Autodesk Fusion 360 part; units mm, degrees
(part 13 of 28)
  line L4632 (91.6329, 89.3668) -> (91.4774, 89.2538)
  line L4633 (91.4774, 89.2538) -> (91.3062, 89.1666)
  line L4634 (91.3062, 89.1666) -> (91.1233, 89.1072)
  line L4635 (91.1233, 89.1072) -> (90.9335, 89.0771)
  line L4636 (90.9335, 89.0771) -> (90.7413, 89.0771)
  line L4637 (90.7413, 89.0771) -> (90.5514, 89.1072)
  line L4638 (90.5514, 89.1072) -> (90.3686, 89.1666)
  line L4639 (90.3686, 89.1666) -> (90.1973, 89.2538)
  line L4640 (90.1973, 89.2538) -> (90.0418, 89.3668)
  line L4641 (90.0418, 89.3668) -> (89.9059, 89.5027)
  line L4642 (89.9059, 89.5027) -> (89.8261, 89.6126)
  line L4643 (89.8261, 89.6126) -> (84.5942, 84.3807)
  line L4644 (84.5942, 84.3807) -> (84.5942, 82.7886)
  line L4645 (84.5942, 82.7886) -> (84.7225, 82.7469)
  line L4646 (84.7225, 82.7469) -> (84.8973, 82.6578)
  line L4647 (84.8973, 82.6578) -> (85.056, 82.5425)
  line L4648 (85.056, 82.5425) -> (85.1947, 82.4038)
  line L4649 (85.1947, 82.4038) -> (85.31, 82.2452)
  line L4650 (85.31, 82.2452) -> (85.399, 82.0704)
  line L4651 (85.399, 82.0704) -> (85.4596, 81.8838)
  line L4652 (85.4596, 81.8838) -> (85.4903, 81.6901)
  line L4653 (85.4903, 81.6901) -> (85.4903, 81.494)
  line L4654 (85.4903, 81.494) -> (85.4596, 81.3002)
  line L4655 (85.4596, 81.3002) -> (85.399, 81.1137)
  line L4656 (85.399, 81.1137) -> (85.31, 80.9389)
  line L4657 (85.31, 80.9389) -> (85.1947, 80.7802)
  line L4658 (85.1947, 80.7802) -> (85.056, 80.6415)
  line L4659 (85.056, 80.6415) -> (84.8973, 80.5262)
  line L4660 (84.8973, 80.5262) -> (84.7225, 80.4372)
  line L4661 (84.7225, 80.4372) -> (84.536, 80.3766)
  line L4662 (84.536, 80.3766) -> (84.3423, 80.3459)
  line L4663 (84.3423, 80.3459) -> (84.2442, 80.342)
  line L4664 (84.2442, 80.342) -> (83.7442, 80.342)
  line L4665 (83.7442, 80.342) -> (83.6461, 80.3459)
  line L4666 (83.6461, 80.3459) -> (83.4524, 80.3766)
  line L4667 (83.4524, 80.3766) -> (83.2658, 80.4372)
  line L4668 (83.2658, 80.4372) -> (83.0911, 80.5262)
  line L4669 (83.0911, 80.5262) -> (82.9324, 80.6415)
  line L4670 (82.9324, 80.6415) -> (82.7937, 80.7802)
  line L4671 (82.7937, 80.7802) -> (82.6784, 80.9389)
  line L4672 (82.6784, 80.9389) -> (82.5893, 81.1137)
  line L4673 (82.5893, 81.1137) -> (82.5287, 81.3002)
  line L4674 (82.5287, 81.3002) -> (82.498, 81.494)
  line L4675 (82.498, 81.494) -> (82.498, 81.6901)
  line L4676 (82.498, 81.6901) -> (82.5287, 81.8838)
  line L4677 (82.5287, 81.8838) -> (82.5893, 82.0704)
  line L4678 (82.5893, 82.0704) -> (82.6784, 82.2452)
  line L4679 (82.6784, 82.2452) -> (82.7937, 82.4038)
  line L4680 (82.7937, 82.4038) -> (82.9324, 82.5425)
  line L4681 (82.9324, 82.5425) -> (83.0911, 82.6578)
  line L4682 (83.0911, 82.6578) -> (83.2658, 82.7469)
  line L4683 (83.2658, 82.7469) -> (83.3942, 82.7886)
  line L4684 (83.3942, 82.7886) -> (83.3942, 84.6292)
  line L4685 (83.3942, 84.6292) -> (83.3993, 84.7075)
  line L4686 (83.3993, 84.7075) -> (83.4399, 84.8588)
  line L4687 (83.4399, 84.8588) -> (83.5182, 84.9944)
  line L4688 (83.5182, 84.9944) -> (83.5699, 85.0535)
  line L4689 (83.5699, 85.0535) -> (89.514, 90.9976)
  line L4690 (89.514, 90.9976) -> (89.5731, 91.0493)
  line L4691 (89.5731, 91.0493) -> (89.6388, 91.0873)
  line L4692 (89.6388, 91.0873) -> (89.6462, 91.1343)
  line L4693 (89.6462, 91.1343) -> (89.7056, 91.3171)
  line L4694 (89.7056, 91.3171) -> (89.7929, 91.4884)
  line L4695 (89.7929, 91.4884) -> (89.9059, 91.6439)
  line L4696 (89.9059, 91.6439) -> (90.0418, 91.7798)
  line L4697 (90.0418, 91.7798) -> (90.1973, 91.8928)
  line L4698 (90.1973, 91.8928) -> (90.3686, 91.9801)
  line L4699 (90.3686, 91.9801) -> (90.5514, 92.0395)
  line L4700 (90.5514, 92.0395) -> (90.7413, 92.0695)
  line L4701 (90.7413, 92.0695) -> (90.9335, 92.0695)
  line L4702 (90.9335, 92.0695) -> (91.1233, 92.0395)
  line L4703 (126.0483, 92.0395) -> (126.2312, 91.9801)
  line L4704 (126.2312, 91.9801) -> (126.4024, 91.8928)
  line L4705 (126.4024, 91.8928) -> (126.5579, 91.7798)
  line L4706 (126.5579, 91.7798) -> (126.6939, 91.6439)
  line L4707 (126.6939, 91.6439) -> (126.8069, 91.4884)
  line L4708 (126.8069, 91.4884) -> (126.8941, 91.3171)
  line L4709 (126.8941, 91.3171) -> (126.9535, 91.1343)
  line L4710 (126.9535, 91.1343) -> (126.9836, 90.9444)
  line L4711 (126.9836, 90.9444) -> (126.9874, 90.8483)
  line L4712 (126.9874, 90.8483) -> (126.9874, 90.2983)
  line L4713 (126.9874, 90.2983) -> (126.9836, 90.2022)
  line L4714 (126.9836, 90.2022) -> (126.9535, 90.0123)
  line L4715 (126.9535, 90.0123) -> (126.8941, 89.8295)
  line L4716 (126.8941, 89.8295) -> (126.8069, 89.6583)
  line L4717 (126.8069, 89.6583) -> (126.6939, 89.5027)
  line L4718 (126.6939, 89.5027) -> (126.5579, 89.3668)
  line L4719 (126.5579, 89.3668) -> (126.4024, 89.2538)
  line L4720 (126.4024, 89.2538) -> (126.2312, 89.1666)
  line L4721 (126.2312, 89.1666) -> (126.0483, 89.1072)
  line L4722 (126.0483, 89.1072) -> (125.8585, 89.0771)
  line L4723 (125.8585, 89.0771) -> (125.6663, 89.0771)
  line L4724 (125.6663, 89.0771) -> (125.4764, 89.1072)
  line L4725 (125.4764, 89.1072) -> (125.2936, 89.1666)
  line L4726 (125.2936, 89.1666) -> (125.1223, 89.2538)
  line L4727 (125.1223, 89.2538) -> (124.9668, 89.3668)
  line L4728 (124.9668, 89.3668) -> (124.8309, 89.5027)
  line L4729 (124.8309, 89.5027) -> (124.7511, 89.6126)
  line L4730 (124.7511, 89.6126) -> (119.5192, 84.3807)
  line L4731 (119.5192, 84.3807) -> (119.5192, 82.7886)
  line L4732 (119.5192, 82.7886) -> (119.6475, 82.7469)
  line L4733 (119.6475, 82.7469) -> (119.8223, 82.6578)
  line L4734 (119.8223, 82.6578) -> (119.981, 82.5425)
  line L4735 (119.981, 82.5425) -> (120.1197, 82.4038)
  line L4736 (120.1197, 82.4038) -> (120.235, 82.2452)
  line L4737 (120.235, 82.2452) -> (120.324, 82.0704)
  line L4738 (120.324, 82.0704) -> (120.3846, 81.8838)
  line L4739 (120.3846, 81.8838) -> (120.4153, 81.6901)
  line L4740 (120.4153, 81.6901) -> (120.4153, 81.494)
  line L4741 (120.4153, 81.494) -> (120.3846, 81.3002)
  line L4742 (120.3846, 81.3002) -> (120.324, 81.1137)
  line L4743 (120.324, 81.1137) -> (120.235, 80.9389)
  line L4744 (120.235, 80.9389) -> (120.1197, 80.7802)
  line L4745 (120.1197, 80.7802) -> (119.981, 80.6415)
  line L4746 (119.981, 80.6415) -> (119.8223, 80.5262)
  line L4747 (119.8223, 80.5262) -> (119.6475, 80.4372)
  line L4748 (119.6475, 80.4372) -> (119.461, 80.3766)
  line L4749 (119.461, 80.3766) -> (119.2673, 80.3459)
  line L4750 (119.2673, 80.3459) -> (119.1692, 80.342)
  line L4751 (119.1692, 80.342) -> (118.6692, 80.342)
  line L4752 (118.6692, 80.342) -> (118.5711, 80.3459)
  line L4753 (118.5711, 80.3459) -> (118.3774, 80.3766)
  line L4754 (118.3774, 80.3766) -> (118.1908, 80.4372)
  line L4755 (118.1908, 80.4372) -> (118.0161, 80.5262)
  line L4756 (118.0161, 80.5262) -> (117.8574, 80.6415)
  line L4757 (117.8574, 80.6415) -> (117.7187, 80.7802)
  line L4758 (117.7187, 80.7802) -> (117.6034, 80.9389)
  line L4759 (117.6034, 80.9389) -> (117.5143, 81.1137)
  line L4760 (117.5143, 81.1137) -> (117.4537, 81.3002)
  line L4761 (117.4537, 81.3002) -> (117.423, 81.494)
  line L4762 (117.423, 81.494) -> (117.423, 81.6901)
  line L4763 (117.423, 81.6901) -> (117.4537, 81.8838)
  line L4764 (117.4537, 81.8838) -> (117.5143, 82.0704)
  line L4765 (117.5143, 82.0704) -> (117.6034, 82.2452)
  line L4766 (117.6034, 82.2452) -> (117.7187, 82.4038)
  line L4767 (117.7187, 82.4038) -> (117.8574, 82.5425)
  line L4768 (117.8574, 82.5425) -> (118.0161, 82.6578)
  line L4769 (118.0161, 82.6578) -> (118.1908, 82.7469)
  line L4770 (118.1908, 82.7469) -> (118.3192, 82.7886)
  line L4771 (118.3192, 82.7886) -> (118.3192, 84.6292)
  line L4772 (118.3192, 84.6292) -> (118.3243, 84.7075)
  line L4773 (118.3243, 84.7075) -> (118.3649, 84.8588)
  line L4774 (118.3649, 84.8588) -> (118.4432, 84.9944)
  line L4775 (118.4432, 84.9944) -> (118.4949, 85.0535)
  line L4776 (118.4949, 85.0535) -> (124.439, 90.9976)
  line L4777 (124.439, 90.9976) -> (124.4981, 91.0493)
  line L4778 (124.4981, 91.0493) -> (124.5638, 91.0873)
  line L4779 (124.5638, 91.0873) -> (124.5712, 91.1343)
  line L4780 (124.5712, 91.1343) -> (124.6306, 91.3171)
  line L4781 (124.6306, 91.3171) -> (124.7179, 91.4884)
  line L4782 (124.7179, 91.4884) -> (124.8309, 91.6439)
  line L4783 (124.8309, 91.6439) -> (124.9668, 91.7798)
  line L4784 (124.9668, 91.7798) -> (125.1223, 91.8928)
  line L4785 (125.1223, 91.8928) -> (125.2936, 91.9801)
  line L4786 (125.2936, 91.9801) -> (125.4764, 92.0395)
  line L4787 (125.4764, 92.0395) -> (125.6663, 92.0695)
  line L4788 (125.6663, 92.0695) -> (125.8585, 92.0695)
  line L4789 (125.8585, 92.0695) -> (126.0483, 92.0395)
  line L4790 (0.0231, 6.9946) -> (0.025, 6.985)
  line L4791 (0.025, 6.985) -> (0.025, 0.025)
  line L4792 (0.025, 0.025) -> (7.62, 0.025)
  line L4793 (7.62, 0.025) -> (7.6296, 0.0231)
  line L4794 (7.6296, 0.0231) -> (7.6431, 0.0096)
  line L4795 (7.6431, 0.0096) -> (7.6431, -0.0096)
  line L4796 (7.6431, -0.0096) -> (7.6296, -0.0231)
  line L4797 (7.6296, -0.0231) -> (7.62, -0.025)
  line L4798 (7.62, -0.025) -> (0.025, -0.025)
  line L4799 (0.025, -0.025) -> (0.025, -5.08)
  line L4800 (0.025, -5.08) -> (0.0231, -5.0896)
  line L4801 (0.0231, -5.0896) -> (0.0096, -5.1031)
  line L4802 (0.0096, -5.1031) -> (-0.0096, -5.1031)
  line L4803 (-0.0096, -5.1031) -> (-0.0231, -5.0896)
  line L4804 (-0.0231, -5.0896) -> (-0.025, -5.08)
  line L4805 (-0.025, -5.08) -> (-0.025, -0.025)
  line L4806 (-0.025, -0.025) -> (-5.08, -0.025)
  line L4807 (-5.08, -0.025) -> (-5.0896, -0.0231)
  line L4808 (-5.0896, -0.0231) -> (-5.1031, -0.0096)
  line L4809 (-5.1031, -0.0096) -> (-5.1031, 0.0096)
  line L4810 (-5.1031, 0.0096) -> (-5.0896, 0.0231)
  line L4811 (-5.0896, 0.0231) -> (-5.08, 0.025)
  line L4812 (-5.08, 0.025) -> (-0.025, 0.025)
  line L4813 (-0.025, 0.025) -> (-0.025, 6.985)
  line L4814 (-0.025, 6.985) -> (-0.0231, 6.9946)
  line L4815 (-0.0231, 6.9946) -> (-0.0096, 7.0081)
  line L4816 (-0.0096, 7.0081) -> (0.0096, 7.0081)
  line L4817 (0.0096, 7.0081) -> (0.0231, 6.9946)
  line L4818 (66.04, 36.855) -> (66.0496, 36.8531)
  line L4819 (66.0496, 36.8531) -> (66.0631, 36.8396)
  line L4820 (66.0631, 36.8396) -> (66.065, 36.83)
  line L4821 (66.065, 36.83) -> (66.065, 5.08)
  line L4822 (66.065, 5.08) -> (66.0631, 5.0704)
  line L4823 (66.0631, 5.0704) -> (66.0496, 5.0569)
  line L4824 (66.0496, 5.0569) -> (66.04, 5.055)
  line L4825 (66.04, 5.055) -> (8.255, 5.055)
  line L4826 (8.255, 5.055) -> (8.2454, 5.0569)
  line L4827 (8.2454, 5.0569) -> (8.2319, 5.0704)
  line L4828 (8.2319, 5.0704) -> (8.23, 5.08)
  line L4829 (8.23, 5.08) -> (8.23, 36.83)
  line L4830 (8.23, 36.83) -> (8.2319, 36.8396)
  line L4831 (8.2319, 36.8396) -> (8.2454, 36.8531)
  line L4832 (8.2454, 36.8531) -> (8.255, 36.855)
  line L4833 (8.255, 36.855) -> (66.04, 36.855)
  line L4834 (8.28, 36.805) -> (8.28, 5.105)
  line L4835 (8.28, 5.105) -> (66.015, 5.105)
  line L4836 (66.015, 5.105) -> (66.015, 36.805)
  line L4837 (66.015, 36.805) -> (62.865, 36.805)
  line L4838 (62.865, 36.805) -> (8.28, 36.805)
  line L4839 (127, 36.855) -> (127.0096, 36.8531)
  line L4840 (127.0096, 36.8531) -> (127.0231, 36.8396)
  line L4841 (127.0231, 36.8396) -> (127.025, 36.83)
  line L4842 (127.025, 36.83) -> (127.025, 5.08)
  line L4843 (127.025, 5.08) -> (127.0231, 5.0704)
  line L4844 (127.0231, 5.0704) -> (127.0096, 5.0569)
  line L4845 (127.0096, 5.0569) -> (127, 5.055)
  line L4846 (127, 5.055) -> (69.215, 5.055)
  line L4847 (69.215, 5.055) -> (69.2054, 5.0569)
  line L4848 (69.2054, 5.0569) -> (69.1919, 5.0704)
  line L4849 (69.1919, 5.0704) -> (69.19, 5.08)
  line L4850 (69.19, 5.08) -> (69.19, 36.83)
  line L4851 (69.19, 36.83) -> (69.1919, 36.8396)
  line L4852 (69.1919, 36.8396) -> (69.2054, 36.8531)
  line L4853 (69.2054, 36.8531) -> (69.215, 36.855)
  line L4854 (69.215, 36.855) -> (127, 36.855)
  line L4855 (69.24, 36.805) -> (69.24, 5.105)
  line L4856 (69.24, 5.105) -> (126.975, 5.105)
  line L4857 (126.975, 5.105) -> (126.975, 36.805)
  line L4858 (126.975, 36.805) -> (123.825, 36.805)
  line L4859 (123.825, 36.805) -> (69.24, 36.805)
  line L4860 (43.18, 97.815) -> (74.93, 97.815)
  line L4861 (74.93, 97.815) -> (74.9396, 97.8131)
  line L4862 (74.9396, 97.8131) -> (74.9531, 97.7996)
  line L4863 (74.9531, 97.7996) -> (74.955, 97.79)
  line L4864 (74.955, 97.79) -> (74.955, 40.005)
  line L4865 (74.955, 40.005) -> (74.9531, 39.9954)
  line L4866 (74.9531, 39.9954) -> (74.9396, 39.9819)
  line L4867 (74.9396, 39.9819) -> (74.93, 39.98)
  line L4868 (74.93, 39.98) -> (43.18, 39.98)
  line L4869 (43.18, 39.98) -> (43.1704, 39.9819)
  line L4870 (43.1704, 39.9819) -> (43.1569, 39.9954)
  line L4871 (43.1569, 39.9954) -> (43.155, 40.005)
  line L4872 (43.155, 40.005) -> (43.155, 97.765)
  line L4873 (40.03, 97.765) -> (40.03, 40.005)
  line L4874 (40.03, 40.005) -> (40.0281, 39.9954)
  line L4875 (40.0281, 39.9954) -> (40.0146, 39.9819)
  line L4876 (40.0146, 39.9819) -> (40.005, 39.98)
  line L4877 (40.005, 39.98) -> (8.255, 39.98)
  line L4878 (8.255, 39.98) -> (8.2454, 39.9819)
  line L4879 (8.2454, 39.9819) -> (8.2319, 39.9954)
  line L4880 (8.2319, 39.9954) -> (8.23, 40.005)
  line L4881 (8.23, 40.005) -> (8.23, 97.79)
  line L4882 (8.23, 97.79) -> (8.2319, 97.7996)
  line L4883 (8.2319, 97.7996) -> (8.2454, 97.8131)
  line L4884 (8.2454, 97.8131) -> (8.255, 97.815)
  line L4885 (8.255, 97.815) -> (40.005, 97.815)
  line L4886 (43.205, 97.765) -> (43.205, 40.03)
  line L4887 (43.205, 40.03) -> (74.905, 40.03)
  line L4888 (74.905, 40.03) -> (74.905, 97.765)
  line L4889 (74.905, 97.765) -> (43.205, 97.765)
  line L4890 (8.28, 97.765) -> (8.28, 40.03)
  line L4891 (8.28, 40.03) -> (39.98, 40.03)
  line L4892 (39.98, 40.03) -> (39.98, 97.765)
  line L4893 (39.98, 97.765) -> (8.28, 97.765)
  line L4894 (109.8646, 97.8131) -> (109.8781, 97.7996)
  line L4895 (109.8781, 97.7996) -> (109.88, 97.79)
  line L4896 (109.88, 97.79) -> (109.88, 40.005)
  line L4897 (109.88, 40.005) -> (109.8781, 39.9954)
  line L4898 (109.8781, 39.9954) -> (109.8646, 39.9819)
  line L4899 (109.8646, 39.9819) -> (109.855, 39.98)
  line L4900 (109.855, 39.98) -> (78.105, 39.98)
  line L4901 (78.105, 39.98) -> (78.0954, 39.9819)
  line L4902 (78.0954, 39.9819) -> (78.0819, 39.9954)
  line L4903 (78.0819, 39.9954) -> (78.08, 40.005)
  line L4904 (78.08, 40.005) -> (78.08, 97.79)
  line L4905 (78.08, 97.79) -> (78.0819, 97.7996)
  line L4906 (78.0819, 97.7996) -> (78.0954, 97.8131)
  line L4907 (78.0954, 97.8131) -> (78.105, 97.815)
  line L4908 (78.105, 97.815) -> (109.855, 97.815)
  line L4909 (109.855, 97.815) -> (109.8646, 97.8131)
  line L4910 (78.13, 97.765) -> (78.13, 40.03)
  line L4911 (78.13, 40.03) -> (109.83, 40.03)
  line L4912 (109.83, 40.03) -> (109.83, 97.765)
  line L4913 (109.83, 97.765) -> (78.13, 97.765)
  line L4914 (144.7896, 97.8131) -> (144.8031, 97.7996)
  line L4915 (144.8031, 97.7996) -> (144.805, 97.79)
  line L4916 (144.805, 97.79) -> (144.805, 40.005)
  line L4917 (144.805, 40.005) -> (144.8031, 39.9954)
  line L4918 (144.8031, 39.9954) -> (144.7896, 39.9819)
  line L4919 (144.7896, 39.9819) -> (144.78, 39.98)
  line L4920 (144.78, 39.98) -> (113.03, 39.98)
  line L4921 (113.03, 39.98) -> (113.0204, 39.9819)
  line L4922 (113.0204, 39.9819) -> (113.0069, 39.9954)
  line L4923 (113.0069, 39.9954) -> (113.005, 40.005)
  line L4924 (113.005, 40.005) -> (113.005, 97.79)
  line L4925 (113.005, 97.79) -> (113.0069, 97.7996)
  line L4926 (113.0069, 97.7996) -> (113.0204, 97.8131)
  line L4927 (113.0204, 97.8131) -> (113.03, 97.815)
  line L4928 (113.03, 97.815) -> (144.78, 97.815)
  line L4929 (144.78, 97.815) -> (144.7896, 97.8131)
  line L4930 (113.055, 97.765) -> (113.055, 40.03)
  line L4931 (113.055, 40.03) -> (144.755, 40.03)
  line L4932 (144.755, 40.03) -> (144.755, 97.765)
  line L4933 (144.755, 97.765) -> (113.055, 97.765)
  arc A0 (27.7068, 75.4403) -> (25.7164, 75.4403) centre (26.7116, 75.4403) ccw
  arc A1 (25.7116, 74.2403) -> (27.7116, 74.2403) centre (26.7116, 74.2403) ccw
  line L4934 (25.7116, 75.4403) -> (25.7164, 75.4403)
  line L4935 (27.7068, 75.4403) -> (27.7116, 75.4403)
  line L4936 (27.7068, 75.4403) -> (27.7116, 74.2403)
  line L4937 (25.7116, 74.2403) -> (25.7164, 75.4403)
  arc A2 (-14.9284, 74.2403) -> (-12.9284, 74.2403) centre (-13.9284, 74.2403) ccw
  line L4938 (-14.9284, 74.2403) -> (-14.9284, 75.4403)
  line L4939 (-12.9332, 75.4403) -> (-12.9284, 74.2403)
  arc A3 (-12.9332, 75.4403) -> (-14.9236, 75.4403) centre (-13.9284, 75.4403) ccw
  spline S0 degree 5 poles (-14.9236, 75.4403) (-14.9236, 75.4399) (-14.9237, 75.4393) (-14.9241, 75.4391) (-14.9252, 75.4396) (-14.9268, 75.4409) (-14.9279, 75.4415) (-14.9283, 75.4412) (-14.9284, 75.4407) (-14.9284, 75.4403) knots 0 0 0 0 0 0 0.2 0.4 0.6 0.8 1 1 1 1 1 1
  constraint perpendicular L2713 L4935
  constraint tangent L2829 A0
  constraint tangent L2820 A1
  constraint collinear L4934 L4935
  constraint coincident A0.centre L4934
  constraint tangent A2 L4938
  constraint tangent A3 S0
sketch "Blinking Light House-PTH-drl_map" plane through (0, 0, 1.4859) normal (0, 0, 1) x (1, 0, 0)
  line L0 (0, 0) -> (0, -5.08)
  line L1 (0, 0) -> (-5.08, 0)
  line L2 (0, 0) -> (7.62, 0)
  line L3 (0, 0) -> (0, 6.985)
  line L4 (123.825, 36.83) -> (127, 36.83)
  line L5 (127, 36.83) -> (127, 5.08)
  line L6 (69.215, 36.83) -> (127, 36.83)
  line L7 (127, 5.08) -> (69.215, 5.08)
  line L8 (69.215, 5.08) -> (69.215, 36.83)
  line L9 (62.865, 36.83) -> (66.04, 36.83)
  line L10 (66.04, 36.83) -> (66.04, 5.08)
  line L11 (8.255, 36.83) -> (66.04, 36.83)
  line L12 (8.255, 5.08) -> (8.255, 36.83)
  line L13 (66.04, 5.08) -> (8.255, 5.08)
  line L14 (113.03, 97.79) -> (144.78, 97.79)
  line L15 (113.03, 40.005) -> (113.03, 97.79)
  line L16 (144.78, 97.79) -> (144.78, 40.005)
  line L17 (144.78, 40.005) -> (113.03, 40.005)
  line L18 (109.855, 97.79) -> (109.855, 40.005)
  line L19 (78.105, 97.79) -> (109.855, 97.79)
  line L20 (109.855, 40.005) -> (78.105, 40.005)
  line L21 (78.105, 40.005) -> (78.105, 97.79)
  line L22 (43.18, 97.79) -> (74.93, 97.79)
  line L23 (74.93, 97.79) -> (74.93, 40.005)
  line L24 (74.93, 40.005) -> (43.18, 40.005)
  line L25 (40.005, 40.005) -> (8.255, 40.005)
  line L26 (43.18, 40.005) -> (43.18, 97.79)
  line L27 (40.005, 97.79) -> (43.18, 97.79)
  line L28 (8.255, 40.005) -> (8.255, 97.79)
  line L29 (40.005, 40.005) -> (8.255, 40.005)
  line L30 (40.005, 97.79) -> (40.005, 40.005)
  line L31 (8.255, 97.79) -> (40.005, 97.79)
  line L32 (-2.4972, -8.2198) -> (-2.4972, -6.2198)
  line L33 (-2.4972, -6.2198) -> (-2.021, -6.2198)
  line L34 (-2.021, -6.2198) -> (-1.7353, -6.3151)
  line L35 (-1.7353, -6.3151) -> (-1.5449, -6.5056)
  line L36 (-1.5449, -6.5056) -> (-1.4496, -6.696)
  line L37 (-1.4496, -6.696) -> (-1.3544, -7.077)
  line L38 (-1.3544, -7.077) -> (-1.3544, -7.3627)
  line L39 (-1.3544, -7.3627) -> (-1.4496, -7.7436)
  line L40 (-1.4496, -7.7436) -> (-1.5449, -7.9341)
  line L41 (-1.5449, -7.9341) -> (-1.7353, -8.1246)
  line L42 (-1.7353, -8.1246) -> (-2.021, -8.2198)
  line L43 (-2.021, -8.2198) -> (-2.4972, -8.2198)
  line L44 (-0.4972, -8.2198) -> (-0.4972, -6.8865)
  line L45 (-0.4972, -7.2675) -> (-0.402, -7.077)
  line L46 (-0.402, -7.077) -> (-0.3068, -6.9817)
  line L47 (-0.3068, -6.9817) -> (-0.1163, -6.8865)
  line L48 (-0.1163, -6.8865) -> (0.0742, -6.8865)
  line L49 (0.7409, -8.2198) -> (0.7409, -6.8865)
  line L50 (0.7409, -6.2198) -> (0.6456, -6.3151)
  line L51 (0.6456, -6.3151) -> (0.7409, -6.4103)
  line L52 (0.7409, -6.4103) -> (0.8361, -6.3151)
  line L53 (0.8361, -6.3151) -> (0.7409, -6.2198)
  line L54 (0.7409, -6.2198) -> (0.7409, -6.4103)
  line L55 (1.979, -8.2198) -> (1.7885, -8.1246)
  line L56 (1.7885, -8.1246) -> (1.6932, -7.9341)
  line L57 (1.6932, -7.9341) -> (1.6932, -6.2198)
  line L58 (3.0266, -8.2198) -> (2.8361, -8.1246)
  line L59 (2.8361, -8.1246) -> (2.7409, -7.9341)
  line L60 (2.7409, -7.9341) -> (2.7409, -6.2198)
  line L61 (5.3123, -8.2198) -> (5.3123, -6.2198)
  line L62 (5.3123, -6.2198) -> (5.979, -7.6484)
  line L63 (5.979, -7.6484) -> (6.6456, -6.2198)
  line L64 (6.6456, -6.2198) -> (6.6456, -8.2198)
  line L65 (8.4551, -8.2198) -> (8.4551, -7.1722)
  line L66 (8.4551, -7.1722) -> (8.3599, -6.9817)
  line L67 (8.3599, -6.9817) -> (8.1694, -6.8865)
  line L68 (8.1694, -6.8865) -> (7.7885, -6.8865)
  line L69 (7.7885, -6.8865) -> (7.598, -6.9817)
  line L70 (8.4551, -8.1246) -> (8.2647, -8.2198)
  line L71 (8.2647, -8.2198) -> (7.7885, -8.2198)
  line L72 (7.7885, -8.2198) -> (7.598, -8.1246)
  line L73 (7.598, -8.1246) -> (7.5028, -7.9341)
  line L74 (7.5028, -7.9341) -> (7.5028, -7.7436)
  line L75 (7.5028, -7.7436) -> (7.598, -7.5532)
  line L76 (7.598, -7.5532) -> (7.7885, -7.4579)
  line L77 (7.7885, -7.4579) -> (8.2647, -7.4579)
  line L78 (8.2647, -7.4579) -> (8.4551, -7.3627)
  line L79 (9.4075, -6.8865) -> (9.4075, -8.8865)
  line L80 (9.4075, -6.9817) -> (9.598, -6.8865)
  line L81 (9.598, -6.8865) -> (9.979, -6.8865)
  line L82 (9.979, -6.8865) -> (10.1694, -6.9817)
  line L83 (10.1694, -6.9817) -> (10.2647, -7.077)
  line L84 (10.2647, -7.077) -> (10.3599, -7.2675)
  line L85 (10.3599, -7.2675) -> (10.3599, -7.8389)
  line L86 (10.3599, -7.8389) -> (10.2647, -8.0294)
  line L87 (10.2647, -8.0294) -> (10.1694, -8.1246)
  line L88 (10.1694, -8.1246) -> (9.979, -8.2198)
  line L89 (9.979, -8.2198) -> (9.598, -8.2198)
  line L90 (9.598, -8.2198) -> (9.4075, -8.1246)
  line L91 (11.2171, -8.0294) -> (11.3123, -8.1246)
  line L92 (11.3123, -8.1246) -> (11.2171, -8.2198)
  line L93 (11.2171, -8.2198) -> (11.1218, -8.1246)
  line L94 (11.1218, -8.1246) -> (11.2171, -8.0294)
  line L95 (11.2171, -8.0294) -> (11.2171, -8.2198)
  line L96 (11.2171, -6.9817) -> (11.3123, -7.077)
  line L97 (11.3123, -7.077) -> (11.2171, -7.1722)
  line L98 (11.2171, -7.1722) -> (11.1218, -7.077)
  line L99 (11.1218, -7.077) -> (11.2171, -6.9817)
  line L100 (11.2171, -6.9817) -> (11.2171, -7.1722)
  line L101 (-5.855, -11.13) -> (-5.105, -11.88)
  line L102 (-5.105, -11.13) -> (-5.855, -11.88)
  line L103 (-2.1163, -10.4198) -> (-1.9258, -10.4198)
  line L104 (-1.9258, -10.4198) -> (-1.7353, -10.5151)
  line L105 (-1.7353, -10.5151) -> (-1.6401, -10.6103)
  line L106 (-1.6401, -10.6103) -> (-1.5449, -10.8008)
  line L107 (-1.5449, -10.8008) -> (-1.4496, -11.1817)
  line L108 (-1.4496, -11.1817) -> (-1.4496, -11.6579)
  line L109 (-1.4496, -11.6579) -> (-1.5449, -12.0389)
  line L110 (-1.5449, -12.0389) -> (-1.6401, -12.2294)
  line L111 (-1.6401, -12.2294) -> (-1.7353, -12.3246)
  line L112 (-1.7353, -12.3246) -> (-1.9258, -12.4198)
  line L113 (-1.9258, -12.4198) -> (-2.1163, -12.4198)
  line L114 (-2.1163, -12.4198) -> (-2.3068, -12.3246)
  line L115 (-2.3068, -12.3246) -> (-2.402, -12.2294)
  line L116 (-2.402, -12.2294) -> (-2.4972, -12.0389)
  line L117 (-2.4972, -12.0389) -> (-2.5925, -11.6579)
  line L118 (-2.5925, -11.6579) -> (-2.5925, -11.1817)
  line L119 (-2.5925, -11.1817) -> (-2.4972, -10.8008)
  line L120 (-2.4972, -10.8008) -> (-2.402, -10.6103)
  line L121 (-2.402, -10.6103) -> (-2.3068, -10.5151)
  line L122 (-2.3068, -10.5151) -> (-2.1163, -10.4198)
  line L123 (-0.5925, -12.2294) -> (-0.4972, -12.3246)
  line L124 (-0.4972, -12.3246) -> (-0.5925, -12.4198)
  line L125 (-0.5925, -12.4198) -> (-0.6877, -12.3246)
  line L126 (-0.6877, -12.3246) -> (-0.5925, -12.2294)
  line L127 (-0.5925, -12.2294) -> (-0.5925, -12.4198)
  line L128 (0.1694, -10.4198) -> (1.5028, -10.4198)
  line L129 (1.5028, -10.4198) -> (0.6456, -12.4198)
  line L130 (3.2171, -10.4198) -> (2.2647, -10.4198)
  line L131 (2.2647, -10.4198) -> (2.1694, -11.3722)
  line L132 (2.1694, -11.3722) -> (2.2647, -11.277)
  line L133 (2.2647, -11.277) -> (2.4551, -11.1817)
  line L134 (2.4551, -11.1817) -> (2.9313, -11.1817)
  line L135 (2.9313, -11.1817) -> (3.1218, -11.277)
  line L136 (3.1218, -11.277) -> (3.2171, -11.3722)
  line L137 (3.2171, -11.3722) -> (3.3123, -11.5627)
  line L138 (3.3123, -11.5627) -> (3.3123, -12.0389)
  line L139 (3.3123, -12.0389) -> (3.2171, -12.2294)
  line L140 (3.2171, -12.2294) -> (3.1218, -12.3246)
  line L141 (3.1218, -12.3246) -> (2.9313, -12.4198)
  line L142 (2.9313, -12.4198) -> (2.4551, -12.4198)
  line L143 (2.4551, -12.4198) -> (2.2647, -12.3246)
  line L144 (2.2647, -12.3246) -> (2.1694, -12.2294)
  line L145 (4.5504, -10.4198) -> (4.7409, -10.4198)
  line L146 (4.7409, -10.4198) -> (4.9313, -10.5151)
  line L147 (4.9313, -10.5151) -> (5.0266, -10.6103)
  line L148 (5.0266, -10.6103) -> (5.1218, -10.8008)
  line L149 (5.1218, -10.8008) -> (5.2171, -11.1817)
  line L150 (5.2171, -11.1817) -> (5.2171, -11.6579)
  line L151 (5.2171, -11.6579) -> (5.1218, -12.0389)
  line L152 (5.1218, -12.0389) -> (5.0266, -12.2294)
  line L153 (5.0266, -12.2294) -> (4.9313, -12.3246)
  line L154 (4.9313, -12.3246) -> (4.7409, -12.4198)
  line L155 (4.7409, -12.4198) -> (4.5504, -12.4198)
  line L156 (4.5504, -12.4198) -> (4.3599, -12.3246)
  line L157 (4.3599, -12.3246) -> (4.2647, -12.2294)
  line L158 (4.2647, -12.2294) -> (4.1694, -12.0389)
  line L159 (4.1694, -12.0389) -> (4.0742, -11.6579)
  line L160 (4.0742, -11.6579) -> (4.0742, -11.1817)
  line L161 (4.0742, -11.1817) -> (4.1694, -10.8008)
  line L162 (4.1694, -10.8008) -> (4.2647, -10.6103)
  line L163 (4.2647, -10.6103) -> (4.3599, -10.5151)
  line L164 (4.3599, -10.5151) -> (4.5504, -10.4198)
  line L165 (6.0742, -12.4198) -> (6.0742, -11.0865)
  line L166 (6.0742, -11.277) -> (6.1694, -11.1817)
  line L167 (6.1694, -11.1817) -> (6.3599, -11.0865)
  line L168 (6.3599, -11.0865) -> (6.6456, -11.0865)
  line L169 (6.6456, -11.0865) -> (6.8361, -11.1817)
  line L170 (6.8361, -11.1817) -> (6.9313, -11.3722)
  line L171 (6.9313, -11.3722) -> (6.9313, -12.4198)
  line L172 (6.9313, -11.3722) -> (7.0266, -11.1817)
  line L173 (7.0266, -11.1817) -> (7.2171, -11.0865)
  line L174 (7.2171, -11.0865) -> (7.5028, -11.0865)
  line L175 (7.5028, -11.0865) -> (7.6932, -11.1817)
  line L176 (7.6932, -11.1817) -> (7.7885, -11.3722)
  line L177 (7.7885, -11.3722) -> (7.7885, -12.4198)
  line L178 (8.7409, -12.4198) -> (8.7409, -11.0865)
  line L179 (8.7409, -11.277) -> (8.8361, -11.1817)
  line L180 (8.8361, -11.1817) -> (9.0266, -11.0865)
  line L181 (9.0266, -11.0865) -> (9.3123, -11.0865)
  line L182 (9.3123, -11.0865) -> (9.5028, -11.1817)
  line L183 (9.5028, -11.1817) -> (9.598, -11.3722)
  line L184 (9.598, -11.3722) -> (9.598, -12.4198)
  line L185 (9.598, -11.3722) -> (9.6932, -11.1817)
  line L186 (9.6932, -11.1817) -> (9.8837, -11.0865)
  line L187 (9.8837, -11.0865) -> (10.1694, -11.0865)
  line L188 (10.1694, -11.0865) -> (10.3599, -11.1817)
  line L189 (10.3599, -11.1817) -> (10.4552, -11.3722)
  line L190 (10.4552, -11.3722) -> (10.4552, -12.4198)
  line L191 (14.3599, -10.3246) -> (12.6456, -12.896)
  line L192 (16.9313, -10.4198) -> (17.1218, -10.4198)
  line L193 (17.1218, -10.4198) -> (17.3123, -10.5151)
  line L194 (17.3123, -10.5151) -> (17.4075, -10.6103)
  line L195 (17.4075, -10.6103) -> (17.5028, -10.8008)
  line L196 (17.5028, -10.8008) -> (17.598, -11.1817)
  line L197 (17.598, -11.1817) -> (17.598, -11.6579)
  line L198 (17.598, -11.6579) -> (17.5028, -12.0389)
  line L199 (17.5028, -12.0389) -> (17.4075, -12.2294)
  line L200 (17.4075, -12.2294) -> (17.3123, -12.3246)
  line L201 (17.3123, -12.3246) -> (17.1218, -12.4198)
  line L202 (17.1218, -12.4198) -> (16.9313, -12.4198)
  line L203 (16.9313, -12.4198) -> (16.7409, -12.3246)
  line L204 (16.7409, -12.3246) -> (16.6456, -12.2294)
  line L205 (16.6456, -12.2294) -> (16.5504, -12.0389)
  line L206 (16.5504, -12.0389) -> (16.4552, -11.6579)
  line L207 (16.4552, -11.6579) -> (16.4552, -11.1817)
  line L208 (16.4552, -11.1817) -> (16.5504, -10.8008)
  line L209 (16.5504, -10.8008) -> (16.6456, -10.6103)
  line L210 (16.6456, -10.6103) -> (16.7409, -10.5151)
  line L211 (16.7409, -10.5151) -> (16.9313, -10.4198)
  line L212 (18.4552, -12.2294) -> (18.5504, -12.3246)
  line L213 (18.5504, -12.3246) -> (18.4552, -12.4198)
  line L214 (18.4552, -12.4198) -> (18.3599, -12.3246)
  line L215 (18.3599, -12.3246) -> (18.4552, -12.2294)
  line L216 (18.4552, -12.2294) -> (18.4552, -12.4198)
  line L217 (19.7885, -10.4198) -> (19.979, -10.4198)
  line L218 (19.979, -10.4198) -> (20.1694, -10.5151)
  line L219 (20.1694, -10.5151) -> (20.2647, -10.6103)
  line L220 (20.2647, -10.6103) -> (20.3599, -10.8008)
  line L221 (20.3599, -10.8008) -> (20.4552, -11.1817)
  line L222 (20.4552, -11.1817) -> (20.4552, -11.6579)
  line L223 (20.4552, -11.6579) -> (20.3599, -12.0389)
  line L224 (20.3599, -12.0389) -> (20.2647, -12.2294)
  line L225 (20.2647, -12.2294) -> (20.1694, -12.3246)
  line L226 (20.1694, -12.3246) -> (19.979, -12.4198)
  line L227 (19.979, -12.4198) -> (19.7885, -12.4198)
  line L228 (19.7885, -12.4198) -> (19.598, -12.3246)
  line L229 (19.598, -12.3246) -> (19.5028, -12.2294)
  line L230 (19.5028, -12.2294) -> (19.4075, -12.0389)
  line L231 (19.4075, -12.0389) -> (19.3123, -11.6579)
  line L232 (19.3123, -11.6579) -> (19.3123, -11.1817)
  line L233 (19.3123, -11.1817) -> (19.4075, -10.8008)
  line L234 (19.4075, -10.8008) -> (19.5028, -10.6103)
  line L235 (19.5028, -10.6103) -> (19.598, -10.5151)
  line L236 (19.598, -10.5151) -> (19.7885, -10.4198)
  line L237 (21.2171, -10.6103) -> (21.3123, -10.5151)
  line L238 (21.3123, -10.5151) -> (21.5028, -10.4198)
  line L239 (21.5028, -10.4198) -> (21.979, -10.4198)
  line L240 (21.979, -10.4198) -> (22.1694, -10.5151)
  line L241 (22.1694, -10.5151) -> (22.2647, -10.6103)
  line L242 (22.2647, -10.6103) -> (22.3599, -10.8008)
  line L243 (22.3599, -10.8008) -> (22.3599, -10.9913)
  line L244 (22.3599, -10.9913) -> (22.2647, -11.277)
  line L245 (22.2647, -11.277) -> (21.1218, -12.4198)
  line L246 (21.1218, -12.4198) -> (22.3599, -12.4198)
  line L247 (23.3123, -12.4198) -> (23.6932, -12.4198)
  line L248 (23.6932, -12.4198) -> (23.8837, -12.3246)
  line L249 (23.8837, -12.3246) -> (23.979, -12.2294)
  line L250 (23.979, -12.2294) -> (24.1694, -11.9436)
  line L251 (24.1694, -11.9436) -> (24.2647, -11.5627)
  line L252 (24.2647, -11.5627) -> (24.2647, -10.8008)
  line L253 (24.2647, -10.8008) -> (24.1694, -10.6103)
  line L254 (24.1694, -10.6103) -> (24.0742, -10.5151)
  line L255 (24.0742, -10.5151) -> (23.8837, -10.4198)
  line L256 (23.8837, -10.4198) -> (23.5028, -10.4198)
  line L257 (23.5028, -10.4198) -> (23.3123, -10.5151)
  line L258 (23.3123, -10.5151) -> (23.2171, -10.6103)
  line L259 (23.2171, -10.6103) -> (23.1218, -10.8008)
  line L260 (23.1218, -10.8008) -> (23.1218, -11.277)
  line L261 (23.1218, -11.277) -> (23.2171, -11.4675)
  line L262 (23.2171, -11.4675) -> (23.3123, -11.5627)
  line L263 (23.3123, -11.5627) -> (23.5028, -11.6579)
  line L264 (23.5028, -11.6579) -> (23.8837, -11.6579)
  line L265 (23.8837, -11.6579) -> (24.0742, -11.5627)
  line L266 (24.0742, -11.5627) -> (24.1694, -11.4675)
  line L267 (24.1694, -11.4675) -> (24.2647, -11.277)
  line L268 (26.0742, -10.4198) -> (25.1218, -10.4198)
  line L269 (25.1218, -10.4198) -> (25.0266, -11.3722)
  line L270 (25.0266, -11.3722) -> (25.1218, -11.277)
  line L271 (25.1218, -11.277) -> (25.3123, -11.1817)
  line L272 (25.3123, -11.1817) -> (25.7885, -11.1817)
  line L273 (25.7885, -11.1817) -> (25.979, -11.277)
  line L274 (25.979, -11.277) -> (26.0742, -11.3722)
  line L275 (26.0742, -11.3722) -> (26.1694, -11.5627)
  line L276 (26.1694, -11.5627) -> (26.1694, -12.0389)
  line L277 (26.1694, -12.0389) -> (26.0742, -12.2294)
  line L278 (26.0742, -12.2294) -> (25.979, -12.3246)
  line L279 (25.979, -12.3246) -> (25.7885, -12.4198)
  line L280 (25.7885, -12.4198) -> (25.3123, -12.4198)
  line L281 (25.3123, -12.4198) -> (25.1218, -12.3246)
  line L282 (25.1218, -12.3246) -> (25.0266, -12.2294)
  line L283 (26.9313, -10.4198) -> (26.9313, -10.8008)
  line L284 (27.6932, -10.4198) -> (27.6932, -10.8008)
  line L285 (30.6456, -13.1817) -> (30.5504, -13.0865)
  line L286 (30.5504, -13.0865) -> (30.3599, -12.8008)
  line L287 (30.3599, -12.8008) -> (30.2647, -12.6103)
  line L288 (30.2647, -12.6103) -> (30.1694, -12.3246)
  line L289 (30.1694, -12.3246) -> (30.0742, -11.8484)
  line L290 (30.0742, -11.8484) -> (30.0742, -11.4675)
  line L291 (30.0742, -11.4675) -> (30.1694, -10.9913)
  line L292 (30.1694, -10.9913) -> (30.2647, -10.7056)
  line L293 (30.2647, -10.7056) -> (30.3599, -10.5151)
  line L294 (30.3599, -10.5151) -> (30.5504, -10.2294)
  line L295 (30.5504, -10.2294) -> (30.6456, -10.1341)
  line L296 (31.2171, -10.4198) -> (32.4552, -10.4198)
  line L297 (32.4552, -10.4198) -> (31.7885, -11.1817)
  line L298 (31.7885, -11.1817) -> (32.0742, -11.1817)
  line L299 (32.0742, -11.1817) -> (32.2647, -11.277)
  line L300 (32.2647, -11.277) -> (32.3599, -11.3722)
  line L301 (32.3599, -11.3722) -> (32.4552, -11.5627)
  line L302 (32.4552, -11.5627) -> (32.4552, -12.0389)
  line L303 (32.4552, -12.0389) -> (32.3599, -12.2294)
  line L304 (32.3599, -12.2294) -> (32.2647, -12.3246)
  line L305 (32.2647, -12.3246) -> (32.0742, -12.4198)
  line L306 (32.0742, -12.4198) -> (31.5028, -12.4198)
  line L307 (31.5028, -12.4198) -> (31.3123, -12.3246)
  line L308 (31.3123, -12.3246) -> (31.2171, -12.2294)
  line L309 (34.1694, -10.4198) -> (33.7885, -10.4198)
  line L310 (33.7885, -10.4198) -> (33.598, -10.5151)
  line L311 (33.598, -10.5151) -> (33.5028, -10.6103)
  line L312 (33.5028, -10.6103) -> (33.3123, -10.896)
  line L313 (33.3123, -10.896) -> (33.2171, -11.277)
  line L314 (33.2171, -11.277) -> (33.2171, -12.0389)
  line L315 (33.2171, -12.0389) -> (33.3123, -12.2294)
  line L316 (33.3123, -12.2294) -> (33.4075, -12.3246)
  line L317 (33.4075, -12.3246) -> (33.598, -12.4198)
  line L318 (33.598, -12.4198) -> (33.979, -12.4198)
  line L319 (33.979, -12.4198) -> (34.1694, -12.3246)
  line L320 (34.1694, -12.3246) -> (34.2647, -12.2294)
  line L321 (34.2647, -12.2294) -> (34.3599, -12.0389)
  line L322 (34.3599, -12.0389) -> (34.3599, -11.5627)
  line L323 (34.3599, -11.5627) -> (34.2647, -11.3722)
  line L324 (34.2647, -11.3722) -> (34.1694, -11.277)
  line L325 (34.1694, -11.277) -> (33.979, -11.1817)
  line L326 (33.979, -11.1817) -> (33.598, -11.1817)
  line L327 (33.598, -11.1817) -> (33.4075, -11.277)
  line L328 (33.4075, -11.277) -> (33.3123, -11.3722)
  line L329 (33.3123, -11.3722) -> (33.2171, -11.5627)
  line L330 (36.7409, -12.4198) -> (36.7409, -10.4198)
  line L331 (37.598, -12.4198) -> (37.598, -11.3722)
  line L332 (37.598, -11.3722) -> (37.5028, -11.1817)
  line L333 (37.5028, -11.1817) -> (37.3123, -11.0865)
  line L334 (37.3123, -11.0865) -> (37.0266, -11.0865)
  line L335 (37.0266, -11.0865) -> (36.8361, -11.1817)
  line L336 (36.8361, -11.1817) -> (36.7409, -11.277)
  line L337 (38.8361, -12.4198) -> (38.6456, -12.3246)
  line L338 (38.6456, -12.3246) -> (38.5504, -12.2294)
  line L339 (38.5504, -12.2294) -> (38.4552, -12.0389)
  line L340 (38.4552, -12.0389) -> (38.4552, -11.4675)
  line L341 (38.4552, -11.4675) -> (38.5504, -11.277)
  line L342 (38.5504, -11.277) -> (38.6456, -11.1817)
  line L343 (38.6456, -11.1817) -> (38.8361, -11.0865)
  line L344 (38.8361, -11.0865) -> (39.1218, -11.0865)
  line L345 (39.1218, -11.0865) -> (39.3123, -11.1817)
  line L346 (39.3123, -11.1817) -> (39.4075, -11.277)
  line L347 (39.4075, -11.277) -> (39.5028, -11.4675)
  line L348 (39.5028, -11.4675) -> (39.5028, -12.0389)
  line L349 (39.5028, -12.0389) -> (39.4075, -12.2294)
  line L350 (39.4075, -12.2294) -> (39.3123, -12.3246)
  line L351 (39.3123, -12.3246) -> (39.1218, -12.4198)
  line L352 (39.1218, -12.4198) -> (38.8361, -12.4198)
  line L353 (40.6456, -12.4198) -> (40.4552, -12.3246)
  line L354 (40.4552, -12.3246) -> (40.3599, -12.1341)
  line L355 (40.3599, -12.1341) -> (40.3599, -10.4198)
  line L356 (42.1694, -12.3246) -> (41.979, -12.4198)
  line L357 (41.979, -12.4198) -> (41.598, -12.4198)
  line L358 (41.598, -12.4198) -> (41.4075, -12.3246)
  line L359 (41.4075, -12.3246) -> (41.3123, -12.1341)
  line L360 (41.3123, -12.1341) -> (41.3123, -11.3722)
  line L361 (41.3123, -11.3722) -> (41.4075, -11.1817)
  line L362 (41.4075, -11.1817) -> (41.598, -11.0865)
  line L363 (41.598, -11.0865) -> (41.979, -11.0865)
  line L364 (41.979, -11.0865) -> (42.1694, -11.1817)
  line L365 (42.1694, -11.1817) -> (42.2647, -11.3722)
  line L366 (42.2647, -11.3722) -> (42.2647, -11.5627)
  line L367 (42.2647, -11.5627) -> (41.3123, -11.7532)
  line L368 (43.0266, -12.3246) -> (43.2171, -12.4198)
  line L369 (43.2171, -12.4198) -> (43.598, -12.4198)
  line L370 (43.598, -12.4198) -> (43.7885, -12.3246)
  line L371 (43.7885, -12.3246) -> (43.8837, -12.1341)
  line L372 (43.8837, -12.1341) -> (43.8837, -12.0389)
  line L373 (43.8837, -12.0389) -> (43.7885, -11.8484)
  line L374 (43.7885, -11.8484) -> (43.598, -11.7532)
  line L375 (43.598, -11.7532) -> (43.3123, -11.7532)
  line L376 (43.3123, -11.7532) -> (43.1218, -11.6579)
  line L377 (43.1218, -11.6579) -> (43.0266, -11.4675)
  line L378 (43.0266, -11.4675) -> (43.0266, -11.3722)
  line L379 (43.0266, -11.3722) -> (43.1218, -11.1817)
  line L380 (43.1218, -11.1817) -> (43.3123, -11.0865)
  line L381 (43.3123, -11.0865) -> (43.598, -11.0865)
  line L382 (43.598, -11.0865) -> (43.7885, -11.1817)
  line L383 (44.5504, -13.1817) -> (44.6456, -13.0865)
  line L384 (44.6456, -13.0865) -> (44.8361, -12.8008)
  line L385 (44.8361, -12.8008) -> (44.9313, -12.6103)
  line L386 (44.9313, -12.6103) -> (45.0266, -12.3246)
  line L387 (45.0266, -12.3246) -> (45.1218, -11.8484)
  line L388 (45.1218, -11.8484) -> (45.1218, -11.4675)
  line L389 (45.1218, -11.4675) -> (45.0266, -10.9913)
  line L390 (45.0266, -10.9913) -> (44.9313, -10.7056)
  line L391 (44.9313, -10.7056) -> (44.8361, -10.5151)
  line L392 (44.8361, -10.5151) -> (44.6456, -10.2294)
  line L393 (44.6456, -10.2294) -> (44.5504, -10.1341)
  circle A0 centre (-5.505, -14.145) radius 0.4
  line L394 (-2.1163, -13.0598) -> (-1.9258, -13.0598)
  line L395 (-1.9258, -13.0598) -> (-1.7353, -13.1551)
  line L396 (-1.7353, -13.1551) -> (-1.6401, -13.2503)
  line L397 (-1.6401, -13.2503) -> (-1.5449, -13.4408)
  line L398 (-1.5449, -13.4408) -> (-1.4496, -13.8217)
  line L399 (-1.4496, -13.8217) -> (-1.4496, -14.2979)
  line L400 (-1.4496, -14.2979) -> (-1.5449, -14.6789)
  line L401 (-1.5449, -14.6789) -> (-1.6401, -14.8694)
  line L402 (-1.6401, -14.8694) -> (-1.7353, -14.9646)
  line L403 (-1.7353, -14.9646) -> (-1.9258, -15.0598)
  line L404 (-1.9258, -15.0598) -> (-2.1163, -15.0598)
  line L405 (-2.1163, -15.0598) -> (-2.3068, -14.9646)
  line L406 (-2.3068, -14.9646) -> (-2.402, -14.8694)
  line L407 (-2.402, -14.8694) -> (-2.4972, -14.6789)
  line L408 (-2.4972, -14.6789) -> (-2.5925, -14.2979)
  line L409 (-2.5925, -14.2979) -> (-2.5925, -13.8217)
  line L410 (-2.5925, -13.8217) -> (-2.4972, -13.4408)
  line L411 (-2.4972, -13.4408) -> (-2.402, -13.2503)
  line L412 (-2.402, -13.2503) -> (-2.3068, -13.1551)
  line L413 (-2.3068, -13.1551) -> (-2.1163, -13.0598)
  line L414 (-0.5925, -14.8694) -> (-0.4972, -14.9646)
  line L415 (-0.4972, -14.9646) -> (-0.5925, -15.0598)
  line L416 (-0.5925, -15.0598) -> (-0.6877, -14.9646)
  line L417 (-0.6877, -14.9646) -> (-0.5925, -14.8694)
  line L418 (-0.5925, -14.8694) -> (-0.5925, -15.0598)
  line L419 (0.6456, -13.917) -> (0.4551, -13.8217)
  line L420 (0.4551, -13.8217) -> (0.3599, -13.7265)
  line L421 (0.3599, -13.7265) -> (0.2647, -13.536)
  line L422 (0.2647, -13.536) -> (0.2647, -13.4408)
  line L423 (0.2647, -13.4408) -> (0.3599, -13.2503)
  line L424 (0.3599, -13.2503) -> (0.4551, -13.1551)
  line L425 (0.4551, -13.1551) -> (0.6456, -13.0598)
  line L426 (0.6456, -13.0598) -> (1.0266, -13.0598)
  line L427 (1.0266, -13.0598) -> (1.2171, -13.1551)
  line L428 (1.2171, -13.1551) -> (1.3123, -13.2503)
  line L429 (1.3123, -13.2503) -> (1.4075, -13.4408)
  line L430 (1.4075, -13.4408) -> (1.4075, -13.536)
  line L431 (1.4075, -13.536) -> (1.3123, -13.7265)
  line L432 (1.3123, -13.7265) -> (1.2171, -13.8217)
  line L433 (1.2171, -13.8217) -> (1.0266, -13.917)
  line L434 (1.0266, -13.917) -> (0.6456, -13.917)
  line L435 (0.6456, -13.917) -> (0.4551, -14.0122)
  line L436 (0.4551, -14.0122) -> (0.3599, -14.1075)
  line L437 (0.3599, -14.1075) -> (0.2647, -14.2979)
  line L438 (0.2647, -14.2979) -> (0.2647, -14.6789)
  line L439 (0.2647, -14.6789) -> (0.3599, -14.8694)
  line L440 (0.3599, -14.8694) -> (0.4551, -14.9646)
  line L441 (0.4551, -14.9646) -> (0.6456, -15.0598)
  line L442 (0.6456, -15.0598) -> (1.0266, -15.0598)
  line L443 (1.0266, -15.0598) -> (1.2171, -14.9646)
  line L444 (1.2171, -14.9646) -> (1.3123, -14.8694)
  line L445 (1.3123, -14.8694) -> (1.4075, -14.6789)
  line L446 (1.4075, -14.6789) -> (1.4075, -14.2979)
  line L447 (1.4075, -14.2979) -> (1.3123, -14.1075)
  line L448 (1.3123, -14.1075) -> (1.2171, -14.0122)
  line L449 (1.2171, -14.0122) -> (1.0266, -13.917)
  line L450 (2.6456, -13.0598) -> (2.8361, -13.0598)
  line L451 (2.8361, -13.0598) -> (3.0266, -13.1551)
  line L452 (3.0266, -13.1551) -> (3.1218, -13.2503)
  line L453 (3.1218, -13.2503) -> (3.2171, -13.4408)
  line L454 (3.2171, -13.4408) -> (3.3123, -13.8217)
  line L455 (3.3123, -13.8217) -> (3.3123, -14.2979)
  line L456 (3.3123, -14.2979) -> (3.2171, -14.6789)
  line L457 (3.2171, -14.6789) -> (3.1218, -14.8694)
  line L458 (3.1218, -14.8694) -> (3.0266, -14.9646)
  line L459 (3.0266, -14.9646) -> (2.8361, -15.0598)
  line L460 (2.8361, -15.0598) -> (2.6456, -15.0598)
  line L461 (2.6456, -15.0598) -> (2.4551, -14.9646)
  line L462 (2.4551, -14.9646) -> (2.3599, -14.8694)
  line L463 (2.3599, -14.8694) -> (2.2647, -14.6789)
  line L464 (2.2647, -14.6789) -> (2.1694, -14.2979)
  line L465 (2.1694, -14.2979) -> (2.1694, -13.8217)
  line L466 (2.1694, -13.8217) -> (2.2647, -13.4408)
  line L467 (2.2647, -13.4408) -> (2.3599, -13.2503)
  line L468 (2.3599, -13.2503) -> (2.4551, -13.1551)
  line L469 (2.4551, -13.1551) -> (2.6456, -13.0598)
  line L470 (4.5504, -13.0598) -> (4.7409, -13.0598)
  line L471 (4.7409, -13.0598) -> (4.9313, -13.1551)
  line L472 (4.9313, -13.1551) -> (5.0266, -13.2503)
  line L473 (5.0266, -13.2503) -> (5.1218, -13.4408)
  line L474 (5.1218, -13.4408) -> (5.2171, -13.8217)
  line L475 (5.2171, -13.8217) -> (5.2171, -14.2979)
  line L476 (5.2171, -14.2979) -> (5.1218, -14.6789)
  line L477 (5.1218, -14.6789) -> (5.0266, -14.8694)
  line L478 (5.0266, -14.8694) -> (4.9313, -14.9646)
  line L479 (4.9313, -14.9646) -> (4.7409, -15.0598)
  line L480 (4.7409, -15.0598) -> (4.5504, -15.0598)
  line L481 (4.5504, -15.0598) -> (4.3599, -14.9646)
  line L482 (4.3599, -14.9646) -> (4.2647, -14.8694)
  line L483 (4.2647, -14.8694) -> (4.1694, -14.6789)
  line L484 (4.1694, -14.6789) -> (4.0742, -14.2979)
  line L485 (4.0742, -14.2979) -> (4.0742, -13.8217)
  line L486 (4.0742, -13.8217) -> (4.1694, -13.4408)
  line L487 (4.1694, -13.4408) -> (4.2647, -13.2503)
  line L488 (4.2647, -13.2503) -> (4.3599, -13.1551)
  line L489 (4.3599, -13.1551) -> (4.5504, -13.0598)
  line L490 (6.0742, -15.0598) -> (6.0742, -13.7265)
  line L491 (6.0742, -13.917) -> (6.1694, -13.8217)
  line L492 (6.1694, -13.8217) -> (6.3599, -13.7265)
  line L493 (6.3599, -13.7265) -> (6.6456, -13.7265)
  line L494 (6.6456, -13.7265) -> (6.8361, -13.8217)
  line L495 (6.8361, -13.8217) -> (6.9313, -14.0122)
  line L496 (6.9313, -14.0122) -> (6.9313, -15.0598)
  line L497 (6.9313, -14.0122) -> (7.0266, -13.8217)
  line L498 (7.0266, -13.8217) -> (7.2171, -13.7265)
  line L499 (7.2171, -13.7265) -> (7.5028, -13.7265)
  line L500 (7.5028, -13.7265) -> (7.6932, -13.8217)
  line L501 (7.6932, -13.8217) -> (7.7885, -14.0122)
  line L502 (7.7885, -14.0122) -> (7.7885, -15.0598)
  line L503 (8.7409, -15.0598) -> (8.7409, -13.7265)
  line L504 (8.7409, -13.917) -> (8.8361, -13.8217)
  line L505 (8.8361, -13.8217) -> (9.0266, -13.7265)
  line L506 (9.0266, -13.7265) -> (9.3123, -13.7265)
  line L507 (9.3123, -13.7265) -> (9.5028, -13.8217)
  line L508 (9.5028, -13.8217) -> (9.598, -14.0122)
  line L509 (9.598, -14.0122) -> (9.598, -15.0598)
  line L510 (9.598, -14.0122) -> (9.6932, -13.8217)
  line L511 (9.6932, -13.8217) -> (9.8837, -13.7265)
  line L512 (9.8837, -13.7265) -> (10.1694, -13.7265)
  line L513 (10.1694, -13.7265) -> (10.3599, -13.8217)
  line L514 (10.3599, -13.8217) -> (10.4552, -14.0122)
  line L515 (10.4552, -14.0122) -> (10.4552, -15.0598)
  line L516 (14.3599, -12.9646) -> (12.6456, -15.536)
  line L517 (16.9313, -13.0598) -> (17.1218, -13.0598)
  line L518 (17.1218, -13.0598) -> (17.3123, -13.1551)
  line L519 (17.3123, -13.1551) -> (17.4075, -13.2503)
  line L520 (17.4075, -13.2503) -> (17.5028, -13.4408)
  line L521 (17.5028, -13.4408) -> (17.598, -13.8217)
  line L522 (17.598, -13.8217) -> (17.598, -14.2979)
  line L523 (17.598, -14.2979) -> (17.5028, -14.6789)
  line L524 (17.5028, -14.6789) -> (17.4075, -14.8694)
  line L525 (17.4075, -14.8694) -> (17.3123, -14.9646)
  line L526 (17.3123, -14.9646) -> (17.1218, -15.0598)
  line L527 (17.1218, -15.0598) -> (16.9313, -15.0598)
  line L528 (16.9313, -15.0598) -> (16.7409, -14.9646)
  line L529 (16.7409, -14.9646) -> (16.6456, -14.8694)
  line L530 (16.6456, -14.8694) -> (16.5504, -14.6789)
  line L531 (16.5504, -14.6789) -> (16.4552, -14.2979)
  line L532 (16.4552, -14.2979) -> (16.4552, -13.8217)
  line L533 (16.4552, -13.8217) -> (16.5504, -13.4408)
  line L534 (16.5504, -13.4408) -> (16.6456, -13.2503)
  line L535 (16.6456, -13.2503) -> (16.7409, -13.1551)
  line L536 (16.7409, -13.1551) -> (16.9313, -13.0598)
  line L537 (18.4552, -14.8694) -> (18.5504, -14.9646)
  line L538 (18.5504, -14.9646) -> (18.4552, -15.0598)
  line L539 (18.4552, -15.0598) -> (18.3599, -14.9646)
  line L540 (18.3599, -14.9646) -> (18.4552, -14.8694)
  line L541 (18.4552, -14.8694) -> (18.4552, -15.0598)
  line L542 (19.7885, -13.0598) -> (19.979, -13.0598)
  line L543 (19.979, -13.0598) -> (20.1694, -13.1551)
  line L544 (20.1694, -13.1551) -> (20.2647, -13.2503)
  line L545 (20.2647, -13.2503) -> (20.3599, -13.4408)
  line L546 (20.3599, -13.4408) -> (20.4552, -13.8217)
  line L547 (20.4552, -13.8217) -> (20.4552, -14.2979)
  line L548 (20.4552, -14.2979) -> (20.3599, -14.6789)
  line L549 (20.3599, -14.6789) -> (20.2647, -14.8694)
  line L550 (20.2647, -14.8694) -> (20.1694, -14.9646)
  line L551 (20.1694, -14.9646) -> (19.979, -15.0598)
  line L552 (19.979, -15.0598) -> (19.7885, -15.0598)
  line L553 (19.7885, -15.0598) -> (19.598, -14.9646)
  line L554 (19.598, -14.9646) -> (19.5028, -14.8694)
  line L555 (19.5028, -14.8694) -> (19.4075, -14.6789)
  line L556 (19.4075, -14.6789) -> (19.3123, -14.2979)
  line L557 (19.3123, -14.2979) -> (19.3123, -13.8217)
  line L558 (19.3123, -13.8217) -> (19.4075, -13.4408)
  line L559 (19.4075, -13.4408) -> (19.5028, -13.2503)
  line L560 (19.5028, -13.2503) -> (19.598, -13.1551)
  line L561 (19.598, -13.1551) -> (19.7885, -13.0598)
  line L562 (21.1218, -13.0598) -> (22.3599, -13.0598)
  line L563 (22.3599, -13.0598) -> (21.6932, -13.8217)
  line L564 (21.6932, -13.8217) -> (21.979, -13.8217)
  line L565 (21.979, -13.8217) -> (22.1694, -13.917)
  line L566 (22.1694, -13.917) -> (22.2647, -14.0122)
  line L567 (22.2647, -14.0122) -> (22.3599, -14.2027)
  line L568 (22.3599, -14.2027) -> (22.3599, -14.6789)
  line L569 (22.3599, -14.6789) -> (22.2647, -14.8694)
  line L570 (22.2647, -14.8694) -> (22.1694, -14.9646)
  line L571 (22.1694, -14.9646) -> (21.979, -15.0598)
  line L572 (21.979, -15.0598) -> (21.4075, -15.0598)
  line L573 (21.4075, -15.0598) -> (21.2171, -14.9646)
  line L574 (21.2171, -14.9646) -> (21.1218, -14.8694)
  line L575 (24.2647, -15.0598) -> (23.1218, -15.0598)
  line L576 (23.6932, -15.0598) -> (23.6932, -13.0598)
  line L577 (23.6932, -13.0598) -> (23.5028, -13.3456)
  line L578 (23.5028, -13.3456) -> (23.3123, -13.536)
  line L579 (23.3123, -13.536) -> (23.1218, -13.6313)
  line L580 (26.0742, -13.0598) -> (25.1218, -13.0598)
  line L581 (25.1218, -13.0598) -> (25.0266, -14.0122)
  line L582 (25.0266, -14.0122) -> (25.1218, -13.917)
  line L583 (25.1218, -13.917) -> (25.3123, -13.8217)
  line L584 (25.3123, -13.8217) -> (25.7885, -13.8217)
  line L585 (25.7885, -13.8217) -> (25.979, -13.917)
  line L586 (25.979, -13.917) -> (26.0742, -14.0122)
  line L587 (26.0742, -14.0122) -> (26.1694, -14.2027)
  line L588 (26.1694, -14.2027) -> (26.1694, -14.6789)
  line L589 (26.1694, -14.6789) -> (26.0742, -14.8694)
  line L590 (26.0742, -14.8694) -> (25.979, -14.9646)
  line L591 (25.979, -14.9646) -> (25.7885, -15.0598)
  line L592 (25.7885, -15.0598) -> (25.3123, -15.0598)
  line L593 (25.3123, -15.0598) -> (25.1218, -14.9646)
  line L594 (25.1218, -14.9646) -> (25.0266, -14.8694)
  line L595 (26.9313, -13.0598) -> (26.9313, -13.4408)
  line L596 (27.6932, -13.0598) -> (27.6932, -13.4408)
  line L597 (30.6456, -15.8217) -> (30.5504, -15.7265)
  line L598 (30.5504, -15.7265) -> (30.3599, -15.4408)
  line L599 (30.3599, -15.4408) -> (30.2647, -15.2503)
  line L600 (30.2647, -15.2503) -> (30.1694, -14.9646)
  line L601 (30.1694, -14.9646) -> (30.0742, -14.4884)
  line L602 (30.0742, -14.4884) -> (30.0742, -14.1075)
  line L603 (30.0742, -14.1075) -> (30.1694, -13.6313)
  line L604 (30.1694, -13.6313) -> (30.2647, -13.3456)
  line L605 (30.2647, -13.3456) -> (30.3599, -13.1551)
  line L606 (30.3599, -13.1551) -> (30.5504, -12.8694)
  line L607 (30.5504, -12.8694) -> (30.6456, -12.7741)
  line L608 (31.2171, -13.0598) -> (32.5504, -13.0598)
  line L609 (32.5504, -13.0598) -> (31.6932, -15.0598)
  line L610 (33.2171, -13.2503) -> (33.3123, -13.1551)
  line L611 (33.3123, -13.1551) -> (33.5028, -13.0598)
  line L612 (33.5028, -13.0598) -> (33.979, -13.0598)
  line L613 (33.979, -13.0598) -> (34.1694, -13.1551)
  line L614 (34.1694, -13.1551) -> (34.2647, -13.2503)